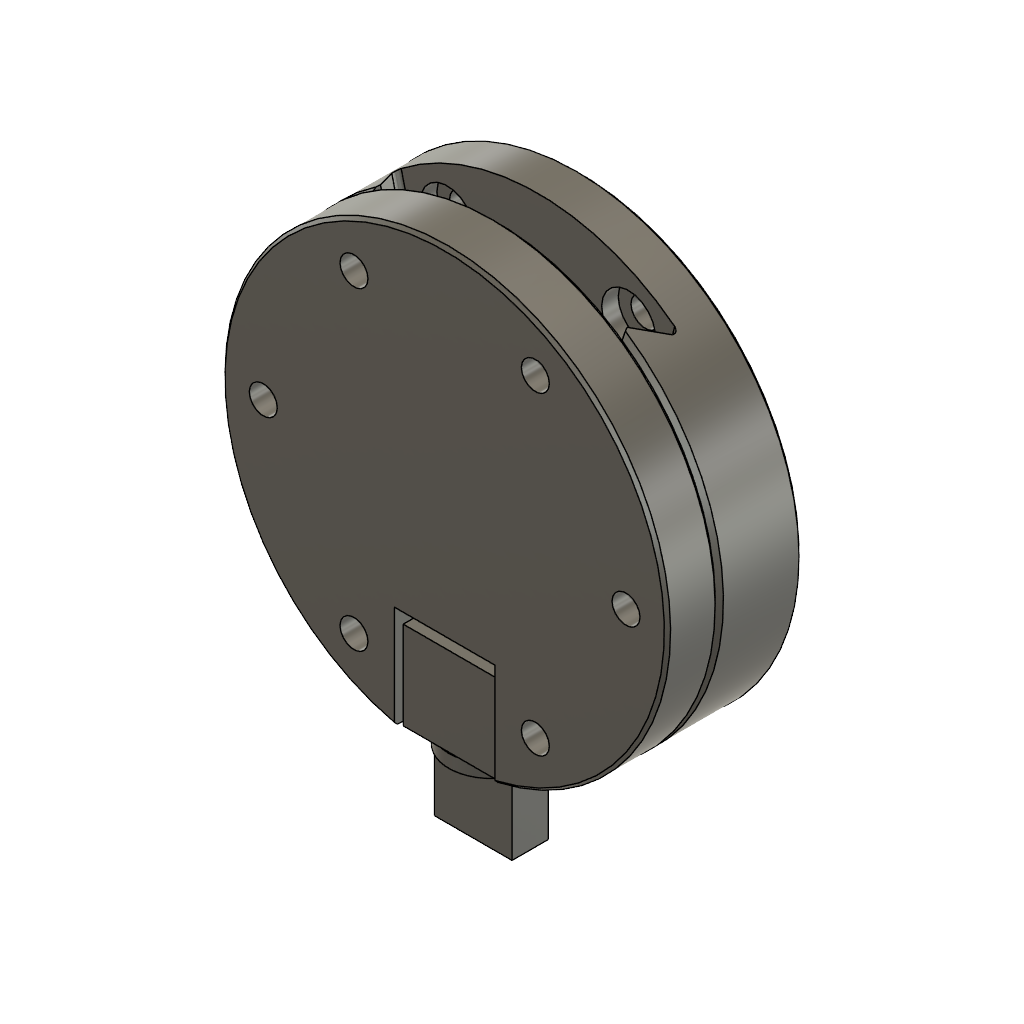
FFBeast_QR (Autodesk Fusion 360 design; units mm, degrees)
part number: 2026-11-14-14-11-19-227
part number: 2026-11-14-14-11-19-448
part number: 2026-11-14-14-11-20-287
part number: 2026-11-14-14-11-22-322
Autodesk Fusion 360 part; units mm, degrees
sketch "Szkic1" plane through (0, 0, 0) normal (0, 0, 1) x (1, 0, 0) in component "A_baza_QR"
  circle A0 centre (0, 0) radius 43
extrude "A_dysk" add sketch "Szkic1" along normal blind 16 makes body 1 in component "A_baza_QR"
ref_plane "Płaszczyzna konstrukcyjna1" through (0, 0, 8) normal (0, 0, 1) x (1, 0, 0) in component "A_baza_QR"
sketch "Szkic2" plane through (0, 0, 8) normal (0, 0, 1) x (1, 0, 0) in component "A_baza_QR"
  line L0 (-13.252, -25) -> (13.252, -25)
  line L1 (13.252, -25) -> (32.2009, 51)
  line L2 (32.2009, 51) -> (-32.2009, 51)
  line L3 (-32.2009, 51) -> (-13.252, -25)
ref_plane "Płaszczyzna konstrukcyjna2" through (0, 0, 16.5) normal (0, 0, 1) x (1, 0, 0) in component "A_baza_QR"
sketch "Szkic3" plane through (0, 0, 16.5) normal (0, 0, 1) x (1, 0, 0) in component "A_baza_QR"
  line L0 (-7.3003, -25) -> (7.3003, -25)
  line L1 (7.3003, -25) -> (26.2492, 51)
  line L2 (26.2492, 51) -> (-26.2492, 51)
  line L3 (-26.2492, 51) -> (-7.3003, -25)
loft "A_kanal_V" cut profiles "Szkic2", "Szkic3" section 1 section 2 bodies 1 in component "A_baza_QR"
fillet "A_promien_nasady_wargi" radius 0.8 2 edges at (-20.47, 3.9497, 8) (20.47, 3.9497, 8) on bodies 1 in component "A_baza_QR"
chamfer "A_faza_wargi" distance 1.7 angle 45 2 edges at (-15.3002, 5.6817, 16) (15.3002, 5.6817, 16) tangent chain off on bodies 1 in component "A_baza_QR"
ref_plane "Płaszczyzna konstrukcyjna3" through (0, 0, 16) normal (0, 0, 1) x (1, 0, 0) in component "A_baza_QR"
sketch "Szkic4" plane through (0, 0, 16) normal (0, 0, 1) x (1, 0, 0) in component "A_baza_QR"
  line L0 (-9, -46) -> (9, -46)
  line L1 (9, -46) -> (9, -25)
  line L2 (9, -25) -> (-9, -25)
  line L3 (-9, -25) -> (-9, -46)
extrude "A_wiezyczka (1)" add sketch "Szkic4" along normal blind 9 bodies 1 in component "A_baza_QR"
sketch "Szkic5" plane through (0, 0, 0) normal (0, 0, 1) x (1, 0, 0) in component "A_baza_QR"
  line L0 (-15, -49) -> (15, -49)
  line L1 (15, -49) -> (15, -42)
  line L2 (15, -42) -> (-15, -42)
  line L3 (-15, -42) -> (-15, -49)
extrude "A_powierzchnia_oporowa" cut sketch "Szkic5" along normal blind 30 bodies 1 in component "A_baza_QR"
sketch "Szkic6" plane through (0, 0, 0) normal (0, 0, 1) x (1, 0, 0) in component "A_baza_QR"
  circle A0 centre (35, 0) radius 2.75
  circle A1 centre (17.5, 30.3109) radius 2.75
  circle A2 centre (-17.5, 30.3109) radius 2.75
  circle A3 centre (-35, 0) radius 2.75
  circle A4 centre (-17.5, -30.3109) radius 2.75
  circle A5 centre (17.5, -30.3109) radius 2.75
extrude "A_otwory_M5 (1)" cut sketch "Szkic6" along normal blind 30 bodies 1 in component "A_baza_QR"
ref_plane "Płaszczyzna konstrukcyjna4" through (0, 0, 4.8) normal (0, 0, 1) x (1, 0, 0) in component "A_baza_QR"
sketch "Szkic7" plane through (0, 0, 4.8) normal (0, 0, 1) x (1, 0, 0) in component "A_baza_QR"
  circle A0 centre (35, 0) radius 5.2
  circle A1 centre (17.5, 30.3109) radius 5.2
  circle A2 centre (-17.5, 30.3109) radius 5.2
  circle A3 centre (-35, 0) radius 5.2
  circle A4 centre (-17.5, -30.3109) radius 5.2
  circle A5 centre (17.5, -30.3109) radius 5.2
extrude "A_poglebienia (1)" cut sketch "Szkic7" along normal blind 30 bodies 1 in component "A_baza_QR"
ref_plane "Płaszczyzna konstrukcyjna5" through (0, -42, 0) normal (0, 1, 0) x (0, 0, 1) in component "A_baza_QR"
sketch "Szkic8" plane through (0, -42, 0) normal (0, 1, 0) x (1, 0, 0) in component "A_baza_QR"
  circle A0 centre (0, -17) radius 4.5
extrude "A_otwor_pod_gwint" cut sketch "Szkic8" along normal blind 18 bodies 1 in component "A_baza_QR"
ref_plane "Płaszczyzna konstrukcyjna6" through (0, -37, 0) normal (0, 1, 0) x (0, 0, 1) in component "A_baza_QR"
sketch "Szkic9" plane through (0, -37, 0) normal (0, 1, 0) x (1, 0, 0) in component "A_baza_QR"
  circle A0 centre (0, -17) radius 5.9
extrude "A_otwor_przelotowy_sruby" cut sketch "Szkic9" along normal blind 13 bodies 1 in component "A_baza_QR"
thread "A_gwint_zabezpieczajacy_Tr12x3" "ISO Metric Trapezoidal Threads 12.0 TR12x3 TR12x3 7H" major diameter 12.5 minor diameter 9.1575 pitch 3 angle 30 modelled right hand crest width 1.1001 on face at (4.4776, -38.6667, 16.5519) crest through (4.5788, -41.25, 17) on bodies 1 in component "A_baza_QR"
chamfer "A_faza_dol" distance 0.6 angle 45 1 edges at (0, 43, 0) tangent chain off on bodies 1 in component "A_baza_QR"
chamfer "A_faza_gora" distance 0.8 angle 45 2 edges at (-42.1899, -8.3075, 16) (42.1899, -8.3075, 16) tangent chain off on bodies 1 in component "A_baza_QR"
ref_plane "Płaszczyzna konstrukcyjna1" through (0, 0, 16) normal (0, 0, 1) x (1, 0, 0) in component "B_adapter_kierownicy"
sketch "Szkic1 (2)" plane through (0, 0, 16) normal (0, 0, 1) x (1, 0, 0) in component "B_adapter_kierownicy"
  circle A0 centre (0, 0) radius 43
extrude "B_plyta" add sketch "Szkic1 (2)" along normal blind 10 separate body makes body 2 in component "B_adapter_kierownicy"
ref_plane "Płaszczyzna konstrukcyjna2" through (0, 0, 8.3) normal (0, 0, 1) x (1, 0, 0) in component "B_adapter_kierownicy"
sketch "Szkic2 (2)" plane through (0, 0, 8.3) normal (0, 0, 1) x (1, 0, 0) in component "B_adapter_kierownicy"
  line L0 (-13.6899, -22) -> (13.6899, -22)
  line L1 (13.6899, -22) -> (25.2837, 24.5)
  line L2 (25.2837, 24.5) -> (-25.2837, 24.5)
  line L3 (-25.2837, 24.5) -> (-13.6899, -22)
ref_plane "Płaszczyzna konstrukcyjna3" through (0, 0, 16.5) normal (0, 0, 1) x (1, 0, 0) in component "B_adapter_kierownicy"
sketch "Szkic3 (2)" plane through (0, 0, 16.5) normal (0, 0, 1) x (1, 0, 0) in component "B_adapter_kierownicy"
  line L0 (-7.9482, -22) -> (7.9482, -22)
  line L1 (7.9482, -22) -> (19.542, 24.5)
  line L2 (19.542, 24.5) -> (-19.542, 24.5)
  line L3 (-19.542, 24.5) -> (-7.9482, -22)
loft "B_pioro_V" add profiles "Szkic2 (2)", "Szkic3 (2)" section 1 section 2 bodies 2 in component "B_adapter_kierownicy"
chamfer "B_faza_spodu_piora" distance 1.2 angle 45 2 edges at (-19.4868, 1.25, 8.3) (19.4868, 1.25, 8.3) tangent chain off on bodies 2 in component "B_adapter_kierownicy"
fillet "B_promien_nasady_piora" radius 0.8 2 edges at (-14.0952, 1.25, 16) (14.0952, 1.25, 16) on bodies 2 in component "B_adapter_kierownicy"
ref_plane "Płaszczyzna konstrukcyjna4" through (0, 0, 16) normal (0, 0, 1) x (1, 0, 0) in component "B_adapter_kierownicy"
sketch "Szkic4 (2)" plane through (0, 0, 16) normal (0, 0, 1) x (1, 0, 0) in component "B_adapter_kierownicy"
  line L0 (-9.7, -48) -> (9.7, -48)
  line L1 (9.7, -48) -> (9.7, -22)
  line L2 (9.7, -22) -> (-9.7, -22)
  line L3 (-9.7, -22) -> (-9.7, -48)
extrude "B_wyciecie_na_wiezyczke" cut sketch "Szkic4 (2)" along normal blind 12 bodies 2 in component "B_adapter_kierownicy"
ref_plane "Płaszczyzna konstrukcyjna5" through (0, 0, 7.3) normal (0, 0, 1) x (1, 0, 0) in component "B_adapter_kierownicy"
sketch "Szkic5 (2)" plane through (0, 0, 7.3) normal (0, 0, 1) x (1, 0, 0) in component "B_adapter_kierownicy"
  circle A0 centre (35, 0) radius 2.7
  circle A1 centre (17.5, 30.3109) radius 2.7
  circle A2 centre (-17.5, 30.3109) radius 2.7
  circle A3 centre (-35, 0) radius 2.7
  circle A4 centre (-17.5, -30.3109) radius 2.7
  circle A5 centre (17.5, -30.3109) radius 2.7
extrude "B_otwory_M5 (1)" cut sketch "Szkic5 (2)" along normal blind 20.7 bodies 2 in component "B_adapter_kierownicy"
ref_plane "Płaszczyzna konstrukcyjna6" through (0, 0, 16) normal (0, 0, 1) x (1, 0, 0) in component "B_adapter_kierownicy"
sketch "Szkic6 (2)" plane through (0, 0, 16) normal (0, 0, 1) x (1, 0, 0) in component "B_adapter_kierownicy"
  line L0 (39.792, 0) -> (37.396, 4.15)
  line L1 (37.396, 4.15) -> (32.604, 4.15)
  line L2 (32.604, 4.15) -> (30.208, 0)
  line L3 (30.208, 0) -> (32.604, -4.15)
  line L4 (32.604, -4.15) -> (37.396, -4.15)
  line L5 (37.396, -4.15) -> (39.792, 0)
  line L6 (22.292, 30.3109) -> (19.896, 34.4609)
  line L7 (19.896, 34.4609) -> (15.104, 34.4609)
  line L8 (15.104, 34.4609) -> (12.708, 30.3109)
  line L9 (12.708, 30.3109) -> (15.104, 26.1609)
  line L10 (15.104, 26.1609) -> (19.896, 26.1609)
  line L11 (19.896, 26.1609) -> (22.292, 30.3109)
  line L12 (-12.708, 30.3109) -> (-15.104, 34.4609)
  line L13 (-15.104, 34.4609) -> (-19.896, 34.4609)
  line L14 (-19.896, 34.4609) -> (-22.292, 30.3109)
  line L15 (-22.292, 30.3109) -> (-19.896, 26.1609)
  line L16 (-19.896, 26.1609) -> (-15.104, 26.1609)
  line L17 (-15.104, 26.1609) -> (-12.708, 30.3109)
  line L18 (-30.208, 0) -> (-32.604, 4.15)
  line L19 (-32.604, 4.15) -> (-37.396, 4.15)
  line L20 (-37.396, 4.15) -> (-39.792, 0)
  line L21 (-39.792, 0) -> (-37.396, -4.15)
  line L22 (-37.396, -4.15) -> (-32.604, -4.15)
  line L23 (-32.604, -4.15) -> (-30.208, 0)
  line L24 (-12.708, -30.3109) -> (-15.104, -26.1609)
  line L25 (-15.104, -26.1609) -> (-19.896, -26.1609)
  line L26 (-19.896, -26.1609) -> (-22.292, -30.3109)
  line L27 (-22.292, -30.3109) -> (-19.896, -34.4609)
  line L28 (-19.896, -34.4609) -> (-15.104, -34.4609)
  line L29 (-15.104, -34.4609) -> (-12.708, -30.3109)
  line L30 (22.292, -30.3109) -> (19.896, -26.1609)
  line L31 (19.896, -26.1609) -> (15.104, -26.1609)
  line L32 (15.104, -26.1609) -> (12.708, -30.3109)
  line L33 (12.708, -30.3109) -> (15.104, -34.4609)
  line L34 (15.104, -34.4609) -> (19.896, -34.4609)
  line L35 (19.896, -34.4609) -> (22.292, -30.3109)
extrude "B_gniazda_nakretek_M5" cut sketch "Szkic6 (2)" along normal blind 6 bodies 2 in component "B_adapter_kierownicy"
ref_plane "Płaszczyzna konstrukcyjna7" through (0, -22, 0) normal (0, 1, 0) x (0, 0, 1) in component "B_adapter_kierownicy"
sketch "Szkic7 (2)" plane through (0, -22, 0) normal (0, 1, 0) x (1, 0, 0) in component "B_adapter_kierownicy"
  circle A0 centre (0, -17) radius 4.5
extrude "B_otwor_pod_gwint" cut sketch "Szkic7 (2)" along normal blind 18 bodies 2 in component "B_adapter_kierownicy"
thread "B_gwint_blokady_Tr12x3" "ISO Metric Trapezoidal Threads 12.0 TR12x3 TR12x3 7H" major diameter 12.5 minor diameter 9.1575 pitch 3 angle 30 modelled right hand crest width 1.1001 on face at (4.4944, -10, 17.2243) crest through (4.5788, -21.25, 17) on bodies 2 in component "B_adapter_kierownicy"
chamfer "B_faza_gora" distance 0.6 angle 45 1 edges at (0, 43, 26) tangent chain off on bodies 2 in component "B_adapter_kierownicy"
chamfer "B_faza_dol" distance 0.8 angle 45 1 edges at (0, 43, 16) tangent chain off on bodies 2 in component "B_adapter_kierownicy"
ref_plane "Płaszczyzna konstrukcyjna1" through (0, -25, 0) normal (0, 1, 0) x (0, 0, 1) in component "C_sruba_blokujaca"
sketch "Szkic1 (3)" plane through (0, -25, 0) normal (0, 1, 0) x (1, 0, 0) in component "C_sruba_blokujaca"
  circle A0 centre (0, -17) radius 5.5
extrude "C_trzpien_gwintu" add sketch "Szkic1 (3)" along normal blind 12 separate body makes body 3 in component "C_sruba_blokujaca"
thread "C_gwint_Tr11x3" "ISO Metric Trapezoidal Threads 11.0 TR11x3 TR11x3 7e" major diameter 10.882 minor diameter 7.325 pitch 3 angle 30 modelled right hand crest width 1.0785 on face at (5.4932, -17, 17.2742) crest through (5.441, -25.75, 17) on bodies 3 in component "C_sruba_blokujaca"
ref_plane "Płaszczyzna konstrukcyjna2" through (0, -13, 0) normal (0, 1, 0) x (0, 0, 1) in component "C_sruba_blokujaca"
sketch "Szkic2 (3)" plane through (0, -13, 0) normal (0, 1, 0) x (1, 0, 0) in component "C_sruba_blokujaca"
  circle A0 centre (0, -17) radius 3.7
extrude "C_pilot (1)" add sketch "Szkic2 (3)" along normal blind 2 bodies 3 in component "C_sruba_blokujaca"
sketch "Szkic3 (3)" plane through (0, -25, 0) normal (0, 1, 0) x (1, 0, 0) in component "C_sruba_blokujaca"
  circle A0 centre (0, -17) radius 4.1
extrude "C_szyjka (1)" add sketch "Szkic3 (3)" against normal blind 17 bodies 3 in component "C_sruba_blokujaca"
ref_plane "Płaszczyzna konstrukcyjna3" through (0, -42, 0) normal (0, 1, 0) x (0, 0, 1) in component "C_sruba_blokujaca"
sketch "Szkic4 (3)" plane through (0, -42, 0) normal (0, 1, 0) x (1, 0, 0) in component "C_sruba_blokujaca"
  circle A0 centre (0, -17) radius 8.2
extrude "C_kolnierz (1)" add sketch "Szkic4 (3)" against normal blind 2.5 bodies 3 in component "C_sruba_blokujaca"
ref_plane "Płaszczyzna konstrukcyjna4" through (0, -44.5, 0) normal (0, 1, 0) x (0, 0, 1) in component "C_sruba_blokujaca"
sketch "Szkic5 (3)" plane through (0, -44.5, 0) normal (0, 1, 0) x (1, 0, 0) in component "C_sruba_blokujaca"
  line L0 (-7.5, -13.5) -> (7.5, -13.5)
  line L1 (7.5, -13.5) -> (7.5, -20.5)
  line L2 (7.5, -20.5) -> (-7.5, -20.5)
  line L3 (-7.5, -20.5) -> (-7.5, -13.5)
extrude "C_skrzydelko (1)" add sketch "Szkic5 (3)" against normal blind 14 bodies 3 in component "C_sruba_blokujaca"
ref_plane "Płaszczyzna konstrukcyjna5" through (0, -60.5, 0) normal (0, 1, 0) x (0, 0, 1) in component "C_sruba_blokujaca"
sketch "Szkic6 (3)" plane through (0, -60.5, 0) normal (0, 1, 0) x (1, 0, 0) in component "C_sruba_blokujaca"
  line L0 (-15, -2) -> (15, -2)
  line L1 (15, -2) -> (15, -13.5)
  line L2 (15, -13.5) -> (-15, -13.5)
  line L3 (-15, -13.5) -> (-15, -2)
extrude "C_plaska_do_druku (1)" cut sketch "Szkic6 (3)" along normal blind 60 bodies 3 in component "C_sruba_blokujaca"
component "A_baza_QR" placed x (1, 0, 0) y (0, 1, 0) z (0, 0, 1) at (0, 0, 0)
component "B_adapter_kierownicy" placed x (1, 0, 0) y (0, 1, 0) z (0, 0, 1) at (0, 0, 0)
component "C_sruba_blokujaca" placed x (1, 0, 0) y (0, 1, 0) z (0, 0, 1) at (0, 0, 0)
equation "qr_dia = 86.0 mm" comment "Srednica zewnetrzna czesci A i B"
equation "qr_pcd = 70.0 mm" comment "Srednica okregu 6 otworow (zmierzona z STL: 70.00)"
equation "qr_a_hole_d = 5.5 mm" comment "Otwor przelotowy M5 w czesci A"
equation "qr_a_cbore_d = 10.4 mm" comment "Poglebienie pod leb M5 ISO 7380 (leb 9.5 mm)"
equation "qr_a_under_head = 4.8 mm" comment "Grubosc materialu pod lbem sruby czesci A"
equation "qr_b_hole_d = 5.4 mm" comment "Otwor przelotowy M5 w czesci B"
equation "qr_b_nut_af = 8.3 mm" comment "Gniazdo nakretki M5 (wymiar pod klucz 8.0 + luz)"
equation "qr_b_nut_depth = 6.0 mm" comment "Glebokosc gniazda nakretki od plaszczyzny styku"
equation "qr_a_floor = 8.0 mm" comment "Grubosc dna kanalu czesci A"
equation "qr_dv_h = 8.0 mm" comment "Wysokosc jaskolczego ogona"
equation "qr_b_plate = 10.0 mm" comment "Grubosc plyty czesci B"
equation "qr_alpha = 14.0 deg" comment "Polkat klina V w planie"
equation "qr_beta = 35.0 deg" comment "Podciecie jaskolczego ogona od pionu"
equation "qr_wf_tip = 14.0 mm" comment "Polszerokosc kanalu przy dnie na wysokosci czubka piora"
equation "qr_y_tip = -22.0 mm" comment "Polozenie czubka piora (nominalne dosuniecie)"
equation "qr_y_wall = -25.0 mm" comment "Sciana koncowa kanalu (szczelina 3 mm = zapas na dosuniecie)"
equation "qr_y_tail = 24.5 mm" comment "Tylny koniec piora"
equation "qr_fit_clr = 0.1 mm" comment "Luz boczny piora na strone (kierunek X) - kalibracja pasowania"
equation "qr_floor_gap = 0.3 mm" comment "Szczelina pioro / dno kanalu"
equation "qr_r_floor = 0.8 mm" comment "Promien u nasady wargi czesci A"
equation "qr_c_lip = 1.7 mm" comment "Faza krawedzi wargi czesci A"
equation "qr_r_root = 0.8 mm" comment "Promien u nasady piora czesci B"
equation "qr_c_tongue = 1.2 mm" comment "Faza dolnych krawedzi piora"
equation "qr_lock_z = 17.0 mm" comment "Wysokosc osi sruby blokujacej"
equation "qr_tower_hw = 9.0 mm" comment "Polszerokosc wiezyczki blokady"
equation "qr_tower_top = 25.0 mm" comment "Gorna powierzchnia wiezyczki"
equation "qr_y_flat = -42.0 mm" comment "Plaska powierzchnia oporowa pokretla"
equation "qr_notch_clr = 0.7 mm" comment "Luz wyciecia czesci B wokol wiezyczki"
equation "qr_thr_pilot = 9.0 mm" comment "Otwor pod gwint wewnetrzny Tr12x3"
equation "qr_thr_depth = 18.0 mm" comment "Glebokosc otworu gwintowanego w piorze"
equation "qr_cap_len = 5.0 mm" comment "Dlugosc gwintu zabezpieczajacego srube przed wypadnieciem"
equation "qr_lock_clr_d = 11.8 mm" comment "Otwor przelotowy sruby w wiezyczce"
equation "qr_scr_thr_d = 11.0 mm" comment "Srednica gwintu sruby (Tr11x3 - celowo mniejsza niz Tr12)"
equation "qr_scr_thr_len = 12.0 mm" comment "Dlugosc gwintu sruby"
equation "qr_scr_neck_d = 8.2 mm" comment "Szyjka sruby"
equation "qr_scr_pilot_d = 7.4 mm" comment "Pilot na czubku sruby"
equation "qr_scr_pilot_len = 2.0 mm" comment "Dlugosc pilota"
equation "qr_scr_collar_d = 16.4 mm" comment "Kolnierz oporowy sruby"
equation "qr_scr_collar_t = 2.5 mm" comment "Grubosc kolnierza"
equation "qr_scr_wing_w = 15.0 mm" comment "Szerokosc skrzydelka"
equation "qr_scr_wing_t = 7.0 mm" comment "Grubosc skrzydelka"
equation "qr_scr_wing_len = 14.0 mm" comment "Dlugosc skrzydelka"
named bodies: "A_baza_QR", "B_adapter_kierownicy", "C_sruba_blokujaca"
